Autodesk Fusion 360 part; units mm, degrees
(part 7 of 9)
equation "d858 = pcbRailThickness"
equation "d860 = pcbLeft + ( pcbWidth - pcbHolePitchX ) / 2 + 1 * pcbHolePitchX"
equation "d861 = pcbFront + ( pcbLength - pcbHolePitchY ) / 2 + 1 * pcbHolePitchY"
equation "d862 = pcbPostDiameter"
equation "d863 = pcbPostHeight"
equation "d865 = pcbLeft + ( pcbWidth - pcbHolePitchX ) / 2 + 1 * pcbHolePitchX"
equation "d866 = pcbFront + ( pcbLength - pcbHolePitchY ) / 2 + 1 * pcbHolePitchY"
equation "d867 = pcbPostPilot"
equation "holderStemX = -0.08972306 mm" comment "Fitted central cylinder X in original holder mesh"
equation "holderStemY = 1.49765268 mm" comment "Fitted central cylinder Y in original holder mesh"
equation "holderWidth = 11.03147984 mm" comment "Exact 3MF X bounding width"
equation "holderLength = 9.74910164 mm" comment "Exact 3MF Y bounding length"
equation "holderHeight = 5.2 mm" comment "Exact 3MF bounding height"
equation "holderTopDepth = shellWall + carrierClearance + 7 mm" comment "Measured flange underside to holder top"
equation "holderBottomDepth = holderTopDepth + holderHeight" comment "Holder lower bearing plane"
equation "holderFit = 0.2 mm" comment "Provisional XY pocket clearance per side"
equation "holderFrameX = 18.4 mm" comment "Receiver outer width"
equation "holderFrameY = 17.6 mm" comment "Receiver outer length preserving OLED clearance"
equation "holderSwitchVoid = 16 mm" comment "Provisional switch lower-body clearance"
equation "holderHookOverlap = 0.3 mm" comment "Prototype retention overlap"
equation "holderHookThickness = 0.8 mm" comment "Snap retaining lip thickness"
equation "holderSpringWidth = 2 mm" comment "External spring width"
equation "holderSpringY = 3.7 mm" comment "Mesh-verified plastic edge band clear of contact exits"
equation "holderLidGap = 0.2 mm" comment "Normal clearance between holder underside and lid support"
equation "d1834 = -( shellWall + carrierClearance + carrierThickness )"
equation "d1836 = -holderTopDepth"
equation "d1838 = -holderBottomDepth"
equation "d1840 = -( shellWall + carrierClearance + carrierThickness + 1 mm )"
equation "d1842 = -( holderBottomDepth + holderLidGap )"
equation "d1844 = bottomThickness"
equation "d1846 = ( layoutGap + keycapSize / 2 + 0 * keyPitch ) - holderFrameX / 2"
equation "d1847 = ( ( keyRowOne ) - holderFrameY / 2 ) + faceOriginV"
equation "d1848 = ( ( ( layoutGap + keycapSize / 2 + 0 * keyPitch ) - holderFrameX / 2 ) + ( holderFrameX ) ) - ( ( layoutGap + keycapSize / 2 + 0 * keyPitch ) - holderFrameX / 2 )"
equation "d1849 = ( ( ( ( keyRowOne ) - holderFrameY / 2 ) + faceOriginV ) + ( holderFrameY ) ) - ( ( ( keyRowOne ) - holderFrameY / 2 ) + faceOriginV )"
equation "d1850 = -( holderBottomDepth + holderHookThickness - shellWall - carrierClearance - carrierThickness )"
equation "d1852 = ( layoutGap + keycapSize / 2 + 0 * keyPitch ) - holderSwitchVoid / 2"
equation "d1853 = ( ( keyRowOne ) - holderSwitchVoid / 2 ) + faceOriginV"
equation "d1854 = ( ( ( layoutGap + keycapSize / 2 + 0 * keyPitch ) - holderSwitchVoid / 2 ) + ( holderSwitchVoid ) ) - ( ( layoutGap + keycapSize / 2 + 0 * keyPitch ) - holderSwitchVoid / 2 )"
equation "d1855 = ( ( ( ( keyRowOne ) - holderSwitchVoid / 2 ) + faceOriginV ) + ( holderSwitchVoid ) ) - ( ( ( keyRowOne ) - holderSwitchVoid / 2 ) + faceOriginV )"
equation "d1856 = -( holderTopDepth - shellWall - carrierClearance - carrierThickness )"
equation "d1858 = ( ( layoutGap + keycapSize / 2 + 0 * keyPitch ) - holderStemX ) - holderWidth / 2 - holderFit"
equation "d1859 = ( ( ( keyRowOne ) - holderStemY ) - holderLength / 2 - holderFit ) + faceOriginV"
equation "d1860 = ( ( ( ( layoutGap + keycapSize / 2 + 0 * keyPitch ) - holderStemX ) - holderWidth / 2 - holderFit ) + ( holderWidth + 2 * holderFit ) ) - ( ( ( layoutGap + keycapSize / 2 + 0 * keyPitch ) - holderStemX ) - holderWidth / 2 - holderFit )"
equation "d1861 = ( ( ( ( ( keyRowOne ) - holderStemY ) - holderLength / 2 - holderFit ) + faceOriginV ) + ( holderLength + 2 * holderFit ) ) - ( ( ( ( keyRowOne ) - holderStemY ) - holderLength / 2 - holderFit ) + faceOriginV )"
equation "d1862 = -( holderHeight + holderHookThickness + 0.2 mm )"
equation "d1864 = ( ( layoutGap + keycapSize / 2 + 0 * keyPitch ) - holderStemX ) - holderFrameX / 2 - 0.1 mm"
equation "d1865 = ( ( ( ( keyRowOne ) - holderStemY ) + holderSpringY ) - holderSpringWidth / 2 - 0.6 mm ) + faceOriginV"
equation "d1866 = ( ( ( ( layoutGap + keycapSize / 2 + 0 * keyPitch ) - holderStemX ) - holderFrameX / 2 - 0.1 mm ) + ( holderFrameX / 2 - holderWidth / 2 - holderFit + 0.1 mm ) ) - ( ( ( layoutGap + keycapSize / 2 + 0 * keyPitch ) - holderStemX ) - holderFrameX / 2 - 0.1 mm )"
equation "d1867 = ( ( ( ( ( ( keyRowOne ) - holderStemY ) + holderSpringY ) - holderSpringWidth / 2 - 0.6 mm ) + faceOriginV ) + ( 0.6 mm ) ) - ( ( ( ( ( keyRowOne ) - holderStemY ) + holderSpringY ) - holderSpringWidth / 2 - 0.6 mm ) + faceOriginV )"
equation "d1868 = -( holderBottomDepth + holderHookThickness - shellWall - carrierClearance - carrierThickness - 1 mm + 0.2 mm )"
equation "d1870 = ( ( layoutGap + keycapSize / 2 + 0 * keyPitch ) - holderStemX ) - holderFrameX / 2 - 0.1 mm"
equation "d1871 = ( ( ( ( keyRowOne ) - holderStemY ) + holderSpringY ) + holderSpringWidth / 2 ) + faceOriginV"
equation "d1872 = ( ( ( ( layoutGap + keycapSize / 2 + 0 * keyPitch ) - holderStemX ) - holderFrameX / 2 - 0.1 mm ) + ( holderFrameX / 2 - holderWidth / 2 - holderFit + 0.1 mm ) ) - ( ( ( layoutGap + keycapSize / 2 + 0 * keyPitch ) - holderStemX ) - holderFrameX / 2 - 0.1 mm )"
equation "d1873 = ( ( ( ( ( ( keyRowOne ) - holderStemY ) + holderSpringY ) + holderSpringWidth / 2 ) + faceOriginV ) + ( 0.6 mm ) ) - ( ( ( ( ( keyRowOne ) - holderStemY ) + holderSpringY ) + holderSpringWidth / 2 ) + faceOriginV )"
equation "d1874 = -( holderBottomDepth + holderHookThickness - shellWall - carrierClearance - carrierThickness - 1 mm + 0.2 mm )"
equation "d1876 = ( ( layoutGap + keycapSize / 2 + 0 * keyPitch ) - holderStemX ) - holderFrameX / 2 + 0.8 mm"
equation "d1877 = ( ( ( ( keyRowOne ) - holderStemY ) + holderSpringY ) - holderSpringWidth / 2 ) + faceOriginV"
equation "d1878 = ( ( ( ( layoutGap + keycapSize / 2 + 0 * keyPitch ) - holderStemX ) - holderFrameX / 2 + 0.8 mm ) + ( holderFrameX / 2 - 0.8 mm - holderWidth / 2 - holderFit ) ) - ( ( ( layoutGap + keycapSize / 2 + 0 * keyPitch ) - holderStemX ) - holderFrameX / 2 + 0.8 mm )"
equation "d1879 = ( ( ( ( ( ( keyRowOne ) - holderStemY ) + holderSpringY ) - holderSpringWidth / 2 ) + faceOriginV ) + ( holderSpringWidth ) ) - ( ( ( ( ( keyRowOne ) - holderStemY ) + holderSpringY ) - holderSpringWidth / 2 ) + faceOriginV )"
equation "d1880 = -( holderHeight + holderHookThickness + 0.2 mm )"
equation "d1882 = ( ( layoutGap + keycapSize / 2 + 0 * keyPitch ) - holderStemX ) - holderFrameX / 2"
equation "d1883 = ( ( ( ( keyRowOne ) - holderStemY ) + holderSpringY ) - holderSpringWidth / 2 ) + faceOriginV"
equation "d1884 = ( ( ( ( layoutGap + keycapSize / 2 + 0 * keyPitch ) - holderStemX ) - holderFrameX / 2 ) + ( holderFrameX / 2 - holderWidth / 2 + holderHookOverlap ) ) - ( ( ( layoutGap + keycapSize / 2 + 0 * keyPitch ) - holderStemX ) - holderFrameX / 2 )"
equation "d1885 = ( ( ( ( ( ( keyRowOne ) - holderStemY ) + holderSpringY ) - holderSpringWidth / 2 ) + faceOriginV ) + ( holderSpringWidth ) ) - ( ( ( ( ( keyRowOne ) - holderStemY ) + holderSpringY ) - holderSpringWidth / 2 ) + faceOriginV )"
equation "d1886 = -( holderHookThickness )"
equation "d1889 = ( ( layoutGap + keycapSize / 2 + 0 * keyPitch ) - holderStemX ) + holderWidth / 2 + holderFit"
equation "d1890 = ( ( ( ( keyRowOne ) - holderStemY ) + holderSpringY ) - holderSpringWidth / 2 - 0.6 mm ) + faceOriginV"
equation "d1891 = ( ( ( ( layoutGap + keycapSize / 2 + 0 * keyPitch ) - holderStemX ) + holderWidth / 2 + holderFit ) + ( holderFrameX / 2 - holderWidth / 2 - holderFit + 0.1 mm ) ) - ( ( ( layoutGap + keycapSize / 2 + 0 * keyPitch ) - holderStemX ) + holderWidth / 2 + holderFit )"
equation "d1892 = ( ( ( ( ( ( keyRowOne ) - holderStemY ) + holderSpringY ) - holderSpringWidth / 2 - 0.6 mm ) + faceOriginV ) + ( 0.6 mm ) ) - ( ( ( ( ( keyRowOne ) - holderStemY ) + holderSpringY ) - holderSpringWidth / 2 - 0.6 mm ) + faceOriginV )"
equation "d1893 = -( holderBottomDepth + holderHookThickness - shellWall - carrierClearance - carrierThickness - 1 mm + 0.2 mm )"
equation "d1895 = ( ( layoutGap + keycapSize / 2 + 0 * keyPitch ) - holderStemX ) + holderWidth / 2 + holderFit"
equation "d1896 = ( ( ( ( keyRowOne ) - holderStemY ) + holderSpringY ) + holderSpringWidth / 2 ) + faceOriginV"
equation "d1897 = ( ( ( ( layoutGap + keycapSize / 2 + 0 * keyPitch ) - holderStemX ) + holderWidth / 2 + holderFit ) + ( holderFrameX / 2 - holderWidth / 2 - holderFit + 0.1 mm ) ) - ( ( ( layoutGap + keycapSize / 2 + 0 * keyPitch ) - holderStemX ) + holderWidth / 2 + holderFit )"
equation "d1898 = ( ( ( ( ( ( keyRowOne ) - holderStemY ) + holderSpringY ) + holderSpringWidth / 2 ) + faceOriginV ) + ( 0.6 mm ) ) - ( ( ( ( ( keyRowOne ) - holderStemY ) + holderSpringY ) + holderSpringWidth / 2 ) + faceOriginV )"
equation "d1899 = -( holderBottomDepth + holderHookThickness - shellWall - carrierClearance - carrierThickness - 1 mm + 0.2 mm )"
equation "d1901 = ( ( layoutGap + keycapSize / 2 + 0 * keyPitch ) - holderStemX ) + holderWidth / 2 + holderFit"
equation "d1902 = ( ( ( ( keyRowOne ) - holderStemY ) + holderSpringY ) - holderSpringWidth / 2 ) + faceOriginV"
equation "d1903 = ( ( ( ( layoutGap + keycapSize / 2 + 0 * keyPitch ) - holderStemX ) + holderWidth / 2 + holderFit ) + ( holderFrameX / 2 - 0.8 mm - holderWidth / 2 - holderFit ) ) - ( ( ( layoutGap + keycapSize / 2 + 0 * keyPitch ) - holderStemX ) + holderWidth / 2 + holderFit )"
equation "d1904 = ( ( ( ( ( ( keyRowOne ) - holderStemY ) + holderSpringY ) - holderSpringWidth / 2 ) + faceOriginV ) + ( holderSpringWidth ) ) - ( ( ( ( ( keyRowOne ) - holderStemY ) + holderSpringY ) - holderSpringWidth / 2 ) + faceOriginV )"
equation "d1905 = -( holderHeight + holderHookThickness + 0.2 mm )"
equation "d1907 = ( ( layoutGap + keycapSize / 2 + 0 * keyPitch ) - holderStemX ) + holderWidth / 2 - holderHookOverlap"
equation "d1908 = ( ( ( ( keyRowOne ) - holderStemY ) + holderSpringY ) - holderSpringWidth / 2 ) + faceOriginV"
equation "d1909 = ( ( ( ( layoutGap + keycapSize / 2 + 0 * keyPitch ) - holderStemX ) + holderWidth / 2 - holderHookOverlap ) + ( holderFrameX / 2 - holderWidth / 2 + holderHookOverlap ) ) - ( ( ( layoutGap + keycapSize / 2 + 0 * keyPitch ) - holderStemX ) + holderWidth / 2 - holderHookOverlap )"
equation "d1910 = ( ( ( ( ( ( keyRowOne ) - holderStemY ) + holderSpringY ) - holderSpringWidth / 2 ) + faceOriginV ) + ( holderSpringWidth ) ) - ( ( ( ( ( keyRowOne ) - holderStemY ) + holderSpringY ) - holderSpringWidth / 2 ) + faceOriginV )"
equation "d1911 = -( holderHookThickness )"
equation "d1914 = ( ( layoutGap + keycapSize / 2 + 0 * keyPitch ) - holderStemX ) + ( -3 mm ) - 0.5 mm"
equation "d1915 = ( ( ( keyRowOne ) - holderStemY ) + 4 mm ) + faceOriginV"
equation "d1916 = ( ( ( ( layoutGap + keycapSize / 2 + 0 * keyPitch ) - holderStemX ) + ( -3 mm ) - 0.5 mm ) + ( 1 mm ) ) - ( ( ( layoutGap + keycapSize / 2 + 0 * keyPitch ) - holderStemX ) + ( -3 mm ) - 0.5 mm )"
equation "d1917 = ( ( ( ( ( keyRowOne ) - holderStemY ) + 4 mm ) + faceOriginV ) + ( holderFrameY / 2 - 4 mm ) ) - ( ( ( ( keyRowOne ) - holderStemY ) + 4 mm ) + faceOriginV )"
equation "d1920 = ( ( layoutGap + keycapSize / 2 + 0 * keyPitch ) - holderStemX ) + ( 3 mm ) - 0.5 mm"
equation "d1921 = ( ( ( keyRowOne ) - holderStemY ) + 4 mm ) + faceOriginV"
equation "d1922 = ( ( ( ( layoutGap + keycapSize / 2 + 0 * keyPitch ) - holderStemX ) + ( 3 mm ) - 0.5 mm ) + ( 1 mm ) ) - ( ( ( layoutGap + keycapSize / 2 + 0 * keyPitch ) - holderStemX ) + ( 3 mm ) - 0.5 mm )"
equation "d1923 = ( ( ( ( ( keyRowOne ) - holderStemY ) + 4 mm ) + faceOriginV ) + ( holderFrameY / 2 - 4 mm ) ) - ( ( ( ( keyRowOne ) - holderStemY ) + 4 mm ) + faceOriginV )"
equation "d1928 = ( ( layoutGap + keycapSize / 2 + 0 * keyPitch ) - holderStemX ) - holderFrameX / 2 - 0.1 mm"
equation "d1929 = ( ( ( keyRowOne ) - holderStemY ) - 5.1 mm ) + faceOriginV"
equation "d1930 = ( ( ( ( layoutGap + keycapSize / 2 + 0 * keyPitch ) - holderStemX ) - holderFrameX / 2 - 0.1 mm ) + ( holderFrameX / 2 - holderWidth / 2 + 0.1 mm ) ) - ( ( ( layoutGap + keycapSize / 2 + 0 * keyPitch ) - holderStemX ) - holderFrameX / 2 - 0.1 mm )"
equation "d1931 = ( ( ( ( ( keyRowOne ) - holderStemY ) - 5.1 mm ) + faceOriginV ) + ( 7.8 mm ) ) - ( ( ( ( keyRowOne ) - holderStemY ) - 5.1 mm ) + faceOriginV )"
equation "d1932 = -( holderHeight + holderHookThickness - 1.2 mm + 0.2 mm )"
equation "d1934 = ( ( layoutGap + keycapSize / 2 + 0 * keyPitch ) - holderStemX ) + holderWidth / 2"
equation "d1935 = ( ( ( keyRowOne ) - holderStemY ) - 5.1 mm ) + faceOriginV"
equation "d1936 = ( ( ( ( layoutGap + keycapSize / 2 + 0 * keyPitch ) - holderStemX ) + holderWidth / 2 ) + ( holderFrameX / 2 - holderWidth / 2 + 0.1 mm ) ) - ( ( ( layoutGap + keycapSize / 2 + 0 * keyPitch ) - holderStemX ) + holderWidth / 2 )"
equation "d1937 = ( ( ( ( ( keyRowOne ) - holderStemY ) - 5.1 mm ) + faceOriginV ) + ( 7.8 mm ) ) - ( ( ( ( keyRowOne ) - holderStemY ) - 5.1 mm ) + faceOriginV )"
equation "d1938 = -( holderHeight + holderHookThickness - 1.2 mm + 0.2 mm )"
equation "d1940 = ( ( layoutGap + keycapSize / 2 + 0 * keyPitch ) - holderStemX ) + ( -2.5 mm ) - 1.2 mm"
equation "d1941 = ( ( ( ( keyRowOne ) - holderStemY ) - 1.2 mm ) * cos(caseTilt) + ( holderBottomDepth + holderLidGap ) * sin(caseTilt) ) - 2.5 mm"
equation "d1942 = ( ( ( ( layoutGap + keycapSize / 2 + 0 * keyPitch ) - holderStemX ) + ( -2.5 mm ) - 1.2 mm ) + ( 2.4 mm ) ) - ( ( ( layoutGap + keycapSize / 2 + 0 * keyPitch ) - holderStemX ) + ( -2.5 mm ) - 1.2 mm )"
equation "d1943 = ( ( ( ( ( ( keyRowOne ) - holderStemY ) - 1.2 mm ) * cos(caseTilt) + ( holderBottomDepth + holderLidGap ) * sin(caseTilt) ) - 2.5 mm ) + ( 5 mm ) ) - ( ( ( ( ( keyRowOne ) - holderStemY ) - 1.2 mm ) * cos(caseTilt) + ( holderBottomDepth + holderLidGap ) * sin(caseTilt) ) - 2.5 mm )"
equation "d1944 = ( frontHeight + ( ( ( keyRowOne ) - holderStemY ) - 1.2 mm ) * sin(caseTilt) - ( holderBottomDepth + holderLidGap ) * cos(caseTilt) ) - bottomThickness - 2 mm"
equation "d1946 = ( ( layoutGap + keycapSize / 2 + 0 * keyPitch ) - holderStemX ) + ( -2.5 mm ) - 0.5 mm"
equation "d1947 = ( ( ( ( keyRowOne ) - holderStemY ) - 1.2 mm ) * cos(caseTilt) + ( holderBottomDepth + holderLidGap ) * sin(caseTilt) ) - 1.5 mm"
equation "d1948 = ( ( ( ( layoutGap + keycapSize / 2 + 0 * keyPitch ) - holderStemX ) + ( -2.5 mm ) - 0.5 mm ) + ( 1 mm ) ) - ( ( ( layoutGap + keycapSize / 2 + 0 * keyPitch ) - holderStemX ) + ( -2.5 mm ) - 0.5 mm )"
equation "d1949 = ( ( ( ( ( ( keyRowOne ) - holderStemY ) - 1.2 mm ) * cos(caseTilt) + ( holderBottomDepth + holderLidGap ) * sin(caseTilt) ) - 1.5 mm ) + ( 3 mm ) ) - ( ( ( ( ( keyRowOne ) - holderStemY ) - 1.2 mm ) * cos(caseTilt) + ( holderBottomDepth + holderLidGap ) * sin(caseTilt) ) - 1.5 mm )"
equation "d1950 = ( frontHeight + ( ( ( keyRowOne ) - holderStemY ) - 1.2 mm ) * sin(caseTilt) - ( holderBottomDepth + holderLidGap ) * cos(caseTilt) ) - bottomThickness + 0.5 mm"
equation "d1952 = ( ( ( layoutGap + keycapSize / 2 + 0 * keyPitch ) - holderStemX ) + ( -2.5 mm ) - 0.5 mm ) - 0.1 mm"
equation "d1953 = ( ( ( ( keyRowOne ) - holderStemY ) - 1.2 mm ) - 2 mm ) + faceOriginV"
equation "d1954 = ( ( ( ( ( layoutGap + keycapSize / 2 + 0 * keyPitch ) - holderStemX ) + ( -2.5 mm ) - 0.5 mm ) - 0.1 mm ) + ( 1.2 mm ) ) - ( ( ( ( layoutGap + keycapSize / 2 + 0 * keyPitch ) - holderStemX ) + ( -2.5 mm ) - 0.5 mm ) - 0.1 mm )"
equation "d1955 = ( ( ( ( ( ( keyRowOne ) - holderStemY ) - 1.2 mm ) - 2 mm ) + faceOriginV ) + ( 4 mm ) ) - ( ( ( ( ( keyRowOne ) - holderStemY ) - 1.2 mm ) - 2 mm ) + faceOriginV )"
equation "d1956 = rearHeight"
equation "d1958 = ( ( layoutGap + keycapSize / 2 + 0 * keyPitch ) - holderStemX ) + ( 2.5 mm ) - 1.2 mm"
equation "d1959 = ( ( ( ( keyRowOne ) - holderStemY ) - 1.2 mm ) * cos(caseTilt) + ( holderBottomDepth + holderLidGap ) * sin(caseTilt) ) - 2.5 mm"
equation "d1960 = ( ( ( ( layoutGap + keycapSize / 2 + 0 * keyPitch ) - holderStemX ) + ( 2.5 mm ) - 1.2 mm ) + ( 2.4 mm ) ) - ( ( ( layoutGap + keycapSize / 2 + 0 * keyPitch ) - holderStemX ) + ( 2.5 mm ) - 1.2 mm )"
equation "d1961 = ( ( ( ( ( ( keyRowOne ) - holderStemY ) - 1.2 mm ) * cos(caseTilt) + ( holderBottomDepth + holderLidGap ) * sin(caseTilt) ) - 2.5 mm ) + ( 5 mm ) ) - ( ( ( ( ( keyRowOne ) - holderStemY ) - 1.2 mm ) * cos(caseTilt) + ( holderBottomDepth + holderLidGap ) * sin(caseTilt) ) - 2.5 mm )"
equation "d1962 = ( frontHeight + ( ( ( keyRowOne ) - holderStemY ) - 1.2 mm ) * sin(caseTilt) - ( holderBottomDepth + holderLidGap ) * cos(caseTilt) ) - bottomThickness - 2 mm"
equation "d1964 = ( ( layoutGap + keycapSize / 2 + 0 * keyPitch ) - holderStemX ) + ( 2.5 mm ) - 0.5 mm"
equation "d1965 = ( ( ( ( keyRowOne ) - holderStemY ) - 1.2 mm ) * cos(caseTilt) + ( holderBottomDepth + holderLidGap ) * sin(caseTilt) ) - 1.5 mm"
equation "d1966 = ( ( ( ( layoutGap + keycapSize / 2 + 0 * keyPitch ) - holderStemX ) + ( 2.5 mm ) - 0.5 mm ) + ( 1 mm ) ) - ( ( ( layoutGap + keycapSize / 2 + 0 * keyPitch ) - holderStemX ) + ( 2.5 mm ) - 0.5 mm )"
equation "d1967 = ( ( ( ( ( ( keyRowOne ) - holderStemY ) - 1.2 mm ) * cos(caseTilt) + ( holderBottomDepth + holderLidGap ) * sin(caseTilt) ) - 1.5 mm ) + ( 3 mm ) ) - ( ( ( ( ( keyRowOne ) - holderStemY ) - 1.2 mm ) * cos(caseTilt) + ( holderBottomDepth + holderLidGap ) * sin(caseTilt) ) - 1.5 mm )"
equation "d1968 = ( frontHeight + ( ( ( keyRowOne ) - holderStemY ) - 1.2 mm ) * sin(caseTilt) - ( holderBottomDepth + holderLidGap ) * cos(caseTilt) ) - bottomThickness + 0.5 mm"
equation "d1970 = ( ( ( layoutGap + keycapSize / 2 + 0 * keyPitch ) - holderStemX ) + ( 2.5 mm ) - 0.5 mm ) - 0.1 mm"
equation "d1971 = ( ( ( ( keyRowOne ) - holderStemY ) - 1.2 mm ) - 2 mm ) + faceOriginV"
equation "d1972 = ( ( ( ( ( layoutGap + keycapSize / 2 + 0 * keyPitch ) - holderStemX ) + ( 2.5 mm ) - 0.5 mm ) - 0.1 mm ) + ( 1.2 mm ) ) - ( ( ( ( layoutGap + keycapSize / 2 + 0 * keyPitch ) - holderStemX ) + ( 2.5 mm ) - 0.5 mm ) - 0.1 mm )"
equation "d1973 = ( ( ( ( ( ( keyRowOne ) - holderStemY ) - 1.2 mm ) - 2 mm ) + faceOriginV ) + ( 4 mm ) ) - ( ( ( ( ( keyRowOne ) - holderStemY ) - 1.2 mm ) - 2 mm ) + faceOriginV )"
equation "d1974 = rearHeight"
equation "d1976 = ( layoutGap + keycapSize / 2 + 1 * keyPitch ) - holderFrameX / 2"
equation "d1977 = ( ( keyRowOne ) - holderFrameY / 2 ) + faceOriginV"
equation "d1978 = ( ( ( layoutGap + keycapSize / 2 + 1 * keyPitch ) - holderFrameX / 2 ) + ( holderFrameX ) ) - ( ( layoutGap + keycapSize / 2 + 1 * keyPitch ) - holderFrameX / 2 )"
equation "d1979 = ( ( ( ( keyRowOne ) - holderFrameY / 2 ) + faceOriginV ) + ( holderFrameY ) ) - ( ( ( keyRowOne ) - holderFrameY / 2 ) + faceOriginV )"
equation "d1980 = -( holderBottomDepth + holderHookThickness - shellWall - carrierClearance - carrierThickness )"
equation "d1982 = ( layoutGap + keycapSize / 2 + 1 * keyPitch ) - holderSwitchVoid / 2"
equation "d1983 = ( ( keyRowOne ) - holderSwitchVoid / 2 ) + faceOriginV"
equation "d1984 = ( ( ( layoutGap + keycapSize / 2 + 1 * keyPitch ) - holderSwitchVoid / 2 ) + ( holderSwitchVoid ) ) - ( ( layoutGap + keycapSize / 2 + 1 * keyPitch ) - holderSwitchVoid / 2 )"
equation "d1985 = ( ( ( ( keyRowOne ) - holderSwitchVoid / 2 ) + faceOriginV ) + ( holderSwitchVoid ) ) - ( ( ( keyRowOne ) - holderSwitchVoid / 2 ) + faceOriginV )"
equation "d1986 = -( holderTopDepth - shellWall - carrierClearance - carrierThickness )"
equation "d1988 = ( ( layoutGap + keycapSize / 2 + 1 * keyPitch ) - holderStemX ) - holderWidth / 2 - holderFit"
equation "d1989 = ( ( ( keyRowOne ) - holderStemY ) - holderLength / 2 - holderFit ) + faceOriginV"
equation "d1990 = ( ( ( ( layoutGap + keycapSize / 2 + 1 * keyPitch ) - holderStemX ) - holderWidth / 2 - holderFit ) + ( holderWidth + 2 * holderFit ) ) - ( ( ( layoutGap + keycapSize / 2 + 1 * keyPitch ) - holderStemX ) - holderWidth / 2 - holderFit )"
equation "d1991 = ( ( ( ( ( keyRowOne ) - holderStemY ) - holderLength / 2 - holderFit ) + faceOriginV ) + ( holderLength + 2 * holderFit ) ) - ( ( ( ( keyRowOne ) - holderStemY ) - holderLength / 2 - holderFit ) + faceOriginV )"
equation "d1992 = -( holderHeight + holderHookThickness + 0.2 mm )"
equation "d1994 = ( ( layoutGap + keycapSize / 2 + 1 * keyPitch ) - holderStemX ) - holderFrameX / 2 - 0.1 mm"
equation "d1995 = ( ( ( ( keyRowOne ) - holderStemY ) + holderSpringY ) - holderSpringWidth / 2 - 0.6 mm ) + faceOriginV"
equation "d1996 = ( ( ( ( layoutGap + keycapSize / 2 + 1 * keyPitch ) - holderStemX ) - holderFrameX / 2 - 0.1 mm ) + ( holderFrameX / 2 - holderWidth / 2 - holderFit + 0.1 mm ) ) - ( ( ( layoutGap + keycapSize / 2 + 1 * keyPitch ) - holderStemX ) - holderFrameX / 2 - 0.1 mm )"
equation "d1997 = ( ( ( ( ( ( keyRowOne ) - holderStemY ) + holderSpringY ) - holderSpringWidth / 2 - 0.6 mm ) + faceOriginV ) + ( 0.6 mm ) ) - ( ( ( ( ( keyRowOne ) - holderStemY ) + holderSpringY ) - holderSpringWidth / 2 - 0.6 mm ) + faceOriginV )"
equation "d1998 = -( holderBottomDepth + holderHookThickness - shellWall - carrierClearance - carrierThickness - 1 mm + 0.2 mm )"
equation "d2000 = ( ( layoutGap + keycapSize / 2 + 1 * keyPitch ) - holderStemX ) - holderFrameX / 2 - 0.1 mm"
equation "d2001 = ( ( ( ( keyRowOne ) - holderStemY ) + holderSpringY ) + holderSpringWidth / 2 ) + faceOriginV"
equation "d2002 = ( ( ( ( layoutGap + keycapSize / 2 + 1 * keyPitch ) - holderStemX ) - holderFrameX / 2 - 0.1 mm ) + ( holderFrameX / 2 - holderWidth / 2 - holderFit + 0.1 mm ) ) - ( ( ( layoutGap + keycapSize / 2 + 1 * keyPitch ) - holderStemX ) - holderFrameX / 2 - 0.1 mm )"
equation "d2003 = ( ( ( ( ( ( keyRowOne ) - holderStemY ) + holderSpringY ) + holderSpringWidth / 2 ) + faceOriginV ) + ( 0.6 mm ) ) - ( ( ( ( ( keyRowOne ) - holderStemY ) + holderSpringY ) + holderSpringWidth / 2 ) + faceOriginV )"
equation "d2004 = -( holderBottomDepth + holderHookThickness - shellWall - carrierClearance - carrierThickness - 1 mm + 0.2 mm )"
equation "d2006 = ( ( layoutGap + keycapSize / 2 + 1 * keyPitch ) - holderStemX ) - holderFrameX / 2 + 0.8 mm"
equation "d2007 = ( ( ( ( keyRowOne ) - holderStemY ) + holderSpringY ) - holderSpringWidth / 2 ) + faceOriginV"
equation "d2008 = ( ( ( ( layoutGap + keycapSize / 2 + 1 * keyPitch ) - holderStemX ) - holderFrameX / 2 + 0.8 mm ) + ( holderFrameX / 2 - 0.8 mm - holderWidth / 2 - holderFit ) ) - ( ( ( layoutGap + keycapSize / 2 + 1 * keyPitch ) - holderStemX ) - holderFrameX / 2 + 0.8 mm )"
equation "d2009 = ( ( ( ( ( ( keyRowOne ) - holderStemY ) + holderSpringY ) - holderSpringWidth / 2 ) + faceOriginV ) + ( holderSpringWidth ) ) - ( ( ( ( ( keyRowOne ) - holderStemY ) + holderSpringY ) - holderSpringWidth / 2 ) + faceOriginV )"
equation "d2010 = -( holderHeight + holderHookThickness + 0.2 mm )"
equation "d2012 = ( ( layoutGap + keycapSize / 2 + 1 * keyPitch ) - holderStemX ) - holderFrameX / 2"
equation "d2013 = ( ( ( ( keyRowOne ) - holderStemY ) + holderSpringY ) - holderSpringWidth / 2 ) + faceOriginV"
equation "d2014 = ( ( ( ( layoutGap + keycapSize / 2 + 1 * keyPitch ) - holderStemX ) - holderFrameX / 2 ) + ( holderFrameX / 2 - holderWidth / 2 + holderHookOverlap ) ) - ( ( ( layoutGap + keycapSize / 2 + 1 * keyPitch ) - holderStemX ) - holderFrameX / 2 )"
equation "d2015 = ( ( ( ( ( ( keyRowOne ) - holderStemY ) + holderSpringY ) - holderSpringWidth / 2 ) + faceOriginV ) + ( holderSpringWidth ) ) - ( ( ( ( ( keyRowOne ) - holderStemY ) + holderSpringY ) - holderSpringWidth / 2 ) + faceOriginV )"
equation "d2016 = -( holderHookThickness )"
equation "d2019 = ( ( layoutGap + keycapSize / 2 + 1 * keyPitch ) - holderStemX ) + holderWidth / 2 + holderFit"
equation "d2020 = ( ( ( ( keyRowOne ) - holderStemY ) + holderSpringY ) - holderSpringWidth / 2 - 0.6 mm ) + faceOriginV"
equation "d2021 = ( ( ( ( layoutGap + keycapSize / 2 + 1 * keyPitch ) - holderStemX ) + holderWidth / 2 + holderFit ) + ( holderFrameX / 2 - holderWidth / 2 - holderFit + 0.1 mm ) ) - ( ( ( layoutGap + keycapSize / 2 + 1 * keyPitch ) - holderStemX ) + holderWidth / 2 + holderFit )"
equation "d2022 = ( ( ( ( ( ( keyRowOne ) - holderStemY ) + holderSpringY ) - holderSpringWidth / 2 - 0.6 mm ) + faceOriginV ) + ( 0.6 mm ) ) - ( ( ( ( ( keyRowOne ) - holderStemY ) + holderSpringY ) - holderSpringWidth / 2 - 0.6 mm ) + faceOriginV )"
equation "d2023 = -( holderBottomDepth + holderHookThickness - shellWall - carrierClearance - carrierThickness - 1 mm + 0.2 mm )"
equation "d2025 = ( ( layoutGap + keycapSize / 2 + 1 * keyPitch ) - holderStemX ) + holderWidth / 2 + holderFit"
equation "d2026 = ( ( ( ( keyRowOne ) - holderStemY ) + holderSpringY ) + holderSpringWidth / 2 ) + faceOriginV"
equation "d2027 = ( ( ( ( layoutGap + keycapSize / 2 + 1 * keyPitch ) - holderStemX ) + holderWidth / 2 + holderFit ) + ( holderFrameX / 2 - holderWidth / 2 - holderFit + 0.1 mm ) ) - ( ( ( layoutGap + keycapSize / 2 + 1 * keyPitch ) - holderStemX ) + holderWidth / 2 + holderFit )"
equation "d2028 = ( ( ( ( ( ( keyRowOne ) - holderStemY ) + holderSpringY ) + holderSpringWidth / 2 ) + faceOriginV ) + ( 0.6 mm ) ) - ( ( ( ( ( keyRowOne ) - holderStemY ) + holderSpringY ) + holderSpringWidth / 2 ) + faceOriginV )"
equation "d2029 = -( holderBottomDepth + holderHookThickness - shellWall - carrierClearance - carrierThickness - 1 mm + 0.2 mm )"
equation "d2031 = ( ( layoutGap + keycapSize / 2 + 1 * keyPitch ) - holderStemX ) + holderWidth / 2 + holderFit"
equation "d2032 = ( ( ( ( keyRowOne ) - holderStemY ) + holderSpringY ) - holderSpringWidth / 2 ) + faceOriginV"
equation "d2033 = ( ( ( ( layoutGap + keycapSize / 2 + 1 * keyPitch ) - holderStemX ) + holderWidth / 2 + holderFit ) + ( holderFrameX / 2 - 0.8 mm - holderWidth / 2 - holderFit ) ) - ( ( ( layoutGap + keycapSize / 2 + 1 * keyPitch ) - holderStemX ) + holderWidth / 2 + holderFit )"
equation "d2034 = ( ( ( ( ( ( keyRowOne ) - holderStemY ) + holderSpringY ) - holderSpringWidth / 2 ) + faceOriginV ) + ( holderSpringWidth ) ) - ( ( ( ( ( keyRowOne ) - holderStemY ) + holderSpringY ) - holderSpringWidth / 2 ) + faceOriginV )"
equation "d2035 = -( holderHeight + holderHookThickness + 0.2 mm )"
equation "d2037 = ( ( layoutGap + keycapSize / 2 + 1 * keyPitch ) - holderStemX ) + holderWidth / 2 - holderHookOverlap"
equation "d2038 = ( ( ( ( keyRowOne ) - holderStemY ) + holderSpringY ) - holderSpringWidth / 2 ) + faceOriginV"
equation "d2039 = ( ( ( ( layoutGap + keycapSize / 2 + 1 * keyPitch ) - holderStemX ) + holderWidth / 2 - holderHookOverlap ) + ( holderFrameX / 2 - holderWidth / 2 + holderHookOverlap ) ) - ( ( ( layoutGap + keycapSize / 2 + 1 * keyPitch ) - holderStemX ) + holderWidth / 2 - holderHookOverlap )"
equation "d2040 = ( ( ( ( ( ( keyRowOne ) - holderStemY ) + holderSpringY ) - holderSpringWidth / 2 ) + faceOriginV ) + ( holderSpringWidth ) ) - ( ( ( ( ( keyRowOne ) - holderStemY ) + holderSpringY ) - holderSpringWidth / 2 ) + faceOriginV )"
equation "d2041 = -( holderHookThickness )"
equation "d2044 = ( ( layoutGap + keycapSize / 2 + 1 * keyPitch ) - holderStemX ) + ( -3 mm ) - 0.5 mm"
equation "d2045 = ( ( ( keyRowOne ) - holderStemY ) + 4 mm ) + faceOriginV"
equation "d2046 = ( ( ( ( layoutGap + keycapSize / 2 + 1 * keyPitch ) - holderStemX ) + ( -3 mm ) - 0.5 mm ) + ( 1 mm ) ) - ( ( ( layoutGap + keycapSize / 2 + 1 * keyPitch ) - holderStemX ) + ( -3 mm ) - 0.5 mm )"
equation "d2047 = ( ( ( ( ( keyRowOne ) - holderStemY ) + 4 mm ) + faceOriginV ) + ( holderFrameY / 2 - 4 mm ) ) - ( ( ( ( keyRowOne ) - holderStemY ) + 4 mm ) + faceOriginV )"
equation "d2050 = ( ( layoutGap + keycapSize / 2 + 1 * keyPitch ) - holderStemX ) + ( 3 mm ) - 0.5 mm"
equation "d2051 = ( ( ( keyRowOne ) - holderStemY ) + 4 mm ) + faceOriginV"
equation "d2052 = ( ( ( ( layoutGap + keycapSize / 2 + 1 * keyPitch ) - holderStemX ) + ( 3 mm ) - 0.5 mm ) + ( 1 mm ) ) - ( ( ( layoutGap + keycapSize / 2 + 1 * keyPitch ) - holderStemX ) + ( 3 mm ) - 0.5 mm )"
equation "d2053 = ( ( ( ( ( keyRowOne ) - holderStemY ) + 4 mm ) + faceOriginV ) + ( holderFrameY / 2 - 4 mm ) ) - ( ( ( ( keyRowOne ) - holderStemY ) + 4 mm ) + faceOriginV )"
equation "d2056 = ( ( layoutGap + keycapSize / 2 + 1 * keyPitch ) - holderStemX ) - holderFrameX / 2 - 0.1 mm"
equation "d2057 = ( ( ( keyRowOne ) - holderStemY ) - 5.1 mm ) + faceOriginV"
equation "d2058 = ( ( ( ( layoutGap + keycapSize / 2 + 1 * keyPitch ) - holderStemX ) - holderFrameX / 2 - 0.1 mm ) + ( holderFrameX / 2 - holderWidth / 2 + 0.1 mm ) ) - ( ( ( layoutGap + keycapSize / 2 + 1 * keyPitch ) - holderStemX ) - holderFrameX / 2 - 0.1 mm )"
equation "d2059 = ( ( ( ( ( keyRowOne ) - holderStemY ) - 5.1 mm ) + faceOriginV ) + ( 7.8 mm ) ) - ( ( ( ( keyRowOne ) - holderStemY ) - 5.1 mm ) + faceOriginV )"
equation "d2060 = -( holderHeight + holderHookThickness - 1.2 mm + 0.2 mm )"
equation "d2062 = ( ( layoutGap + keycapSize / 2 + 1 * keyPitch ) - holderStemX ) + holderWidth / 2"
equation "d2063 = ( ( ( keyRowOne ) - holderStemY ) - 5.1 mm ) + faceOriginV"
equation "d2064 = ( ( ( ( layoutGap + keycapSize / 2 + 1 * keyPitch ) - holderStemX ) + holderWidth / 2 ) + ( holderFrameX / 2 - holderWidth / 2 + 0.1 mm ) ) - ( ( ( layoutGap + keycapSize / 2 + 1 * keyPitch ) - holderStemX ) + holderWidth / 2 )"
equation "d2065 = ( ( ( ( ( keyRowOne ) - holderStemY ) - 5.1 mm ) + faceOriginV ) + ( 7.8 mm ) ) - ( ( ( ( keyRowOne ) - holderStemY ) - 5.1 mm ) + faceOriginV )"
equation "d2066 = -( holderHeight + holderHookThickness - 1.2 mm + 0.2 mm )"
equation "d2068 = ( ( layoutGap + keycapSize / 2 + 1 * keyPitch ) - holderStemX ) + ( -2.5 mm ) - 1.2 mm"
equation "d2069 = ( ( ( ( keyRowOne ) - holderStemY ) - 1.2 mm ) * cos(caseTilt) + ( holderBottomDepth + holderLidGap ) * sin(caseTilt) ) - 2.5 mm"
equation "d2070 = ( ( ( ( layoutGap + keycapSize / 2 + 1 * keyPitch ) - holderStemX ) + ( -2.5 mm ) - 1.2 mm ) + ( 2.4 mm ) ) - ( ( ( layoutGap + keycapSize / 2 + 1 * keyPitch ) - holderStemX ) + ( -2.5 mm ) - 1.2 mm )"
equation "d2071 = ( ( ( ( ( ( keyRowOne ) - holderStemY ) - 1.2 mm ) * cos(caseTilt) + ( holderBottomDepth + holderLidGap ) * sin(caseTilt) ) - 2.5 mm ) + ( 5 mm ) ) - ( ( ( ( ( keyRowOne ) - holderStemY ) - 1.2 mm ) * cos(caseTilt) + ( holderBottomDepth + holderLidGap ) * sin(caseTilt) ) - 2.5 mm )"
equation "d2072 = ( frontHeight + ( ( ( keyRowOne ) - holderStemY ) - 1.2 mm ) * sin(caseTilt) - ( holderBottomDepth + holderLidGap ) * cos(caseTilt) ) - bottomThickness - 2 mm"
equation "d2074 = ( ( layoutGap + keycapSize / 2 + 1 * keyPitch ) - holderStemX ) + ( -2.5 mm ) - 0.5 mm"
equation "d2075 = ( ( ( ( keyRowOne ) - holderStemY ) - 1.2 mm ) * cos(caseTilt) + ( holderBottomDepth + holderLidGap ) * sin(caseTilt) ) - 1.5 mm"
equation "d2076 = ( ( ( ( layoutGap + keycapSize / 2 + 1 * keyPitch ) - holderStemX ) + ( -2.5 mm ) - 0.5 mm ) + ( 1 mm ) ) - ( ( ( layoutGap + keycapSize / 2 + 1 * keyPitch ) - holderStemX ) + ( -2.5 mm ) - 0.5 mm )"
equation "d2077 = ( ( ( ( ( ( keyRowOne ) - holderStemY ) - 1.2 mm ) * cos(caseTilt) + ( holderBottomDepth + holderLidGap ) * sin(caseTilt) ) - 1.5 mm ) + ( 3 mm ) ) - ( ( ( ( ( keyRowOne ) - holderStemY ) - 1.2 mm ) * cos(caseTilt) + ( holderBottomDepth + holderLidGap ) * sin(caseTilt) ) - 1.5 mm )"
equation "d2078 = ( frontHeight + ( ( ( keyRowOne ) - holderStemY ) - 1.2 mm ) * sin(caseTilt) - ( holderBottomDepth + holderLidGap ) * cos(caseTilt) ) - bottomThickness + 0.5 mm"
equation "d2080 = ( ( ( layoutGap + keycapSize / 2 + 1 * keyPitch ) - holderStemX ) + ( -2.5 mm ) - 0.5 mm ) - 0.1 mm"
equation "d2081 = ( ( ( ( keyRowOne ) - holderStemY ) - 1.2 mm ) - 2 mm ) + faceOriginV"
equation "d2082 = ( ( ( ( ( layoutGap + keycapSize / 2 + 1 * keyPitch ) - holderStemX ) + ( -2.5 mm ) - 0.5 mm ) - 0.1 mm ) + ( 1.2 mm ) ) - ( ( ( ( layoutGap + keycapSize / 2 + 1 * keyPitch ) - holderStemX ) + ( -2.5 mm ) - 0.5 mm ) - 0.1 mm )"
equation "d2083 = ( ( ( ( ( ( keyRowOne ) - holderStemY ) - 1.2 mm ) - 2 mm ) + faceOriginV ) + ( 4 mm ) ) - ( ( ( ( ( keyRowOne ) - holderStemY ) - 1.2 mm ) - 2 mm ) + faceOriginV )"
equation "d2084 = rearHeight"
equation "d2086 = ( ( layoutGap + keycapSize / 2 + 1 * keyPitch ) - holderStemX ) + ( 2.5 mm ) - 1.2 mm"
equation "d2087 = ( ( ( ( keyRowOne ) - holderStemY ) - 1.2 mm ) * cos(caseTilt) + ( holderBottomDepth + holderLidGap ) * sin(caseTilt) ) - 2.5 mm"
equation "d2088 = ( ( ( ( layoutGap + keycapSize / 2 + 1 * keyPitch ) - holderStemX ) + ( 2.5 mm ) - 1.2 mm ) + ( 2.4 mm ) ) - ( ( ( layoutGap + keycapSize / 2 + 1 * keyPitch ) - holderStemX ) + ( 2.5 mm ) - 1.2 mm )"
equation "d2089 = ( ( ( ( ( ( keyRowOne ) - holderStemY ) - 1.2 mm ) * cos(caseTilt) + ( holderBottomDepth + holderLidGap ) * sin(caseTilt) ) - 2.5 mm ) + ( 5 mm ) ) - ( ( ( ( ( keyRowOne ) - holderStemY ) - 1.2 mm ) * cos(caseTilt) + ( holderBottomDepth + holderLidGap ) * sin(caseTilt) ) - 2.5 mm )"
equation "d2090 = ( frontHeight + ( ( ( keyRowOne ) - holderStemY ) - 1.2 mm ) * sin(caseTilt) - ( holderBottomDepth + holderLidGap ) * cos(caseTilt) ) - bottomThickness - 2 mm"
equation "d2092 = ( ( layoutGap + keycapSize / 2 + 1 * keyPitch ) - holderStemX ) + ( 2.5 mm ) - 0.5 mm"
equation "d2093 = ( ( ( ( keyRowOne ) - holderStemY ) - 1.2 mm ) * cos(caseTilt) + ( holderBottomDepth + holderLidGap ) * sin(caseTilt) ) - 1.5 mm"
equation "d2094 = ( ( ( ( layoutGap + keycapSize / 2 + 1 * keyPitch ) - holderStemX ) + ( 2.5 mm ) - 0.5 mm ) + ( 1 mm ) ) - ( ( ( layoutGap + keycapSize / 2 + 1 * keyPitch ) - holderStemX ) + ( 2.5 mm ) - 0.5 mm )"
equation "d2095 = ( ( ( ( ( ( keyRowOne ) - holderStemY ) - 1.2 mm ) * cos(caseTilt) + ( holderBottomDepth + holderLidGap ) * sin(caseTilt) ) - 1.5 mm ) + ( 3 mm ) ) - ( ( ( ( ( keyRowOne ) - holderStemY ) - 1.2 mm ) * cos(caseTilt) + ( holderBottomDepth + holderLidGap ) * sin(caseTilt) ) - 1.5 mm )"
equation "d2096 = ( frontHeight + ( ( ( keyRowOne ) - holderStemY ) - 1.2 mm ) * sin(caseTilt) - ( holderBottomDepth + holderLidGap ) * cos(caseTilt) ) - bottomThickness + 0.5 mm"
equation "d2098 = ( ( ( layoutGap + keycapSize / 2 + 1 * keyPitch ) - holderStemX ) + ( 2.5 mm ) - 0.5 mm ) - 0.1 mm"
equation "d2099 = ( ( ( ( keyRowOne ) - holderStemY ) - 1.2 mm ) - 2 mm ) + faceOriginV"
equation "d2100 = ( ( ( ( ( layoutGap + keycapSize / 2 + 1 * keyPitch ) - holderStemX ) + ( 2.5 mm ) - 0.5 mm ) - 0.1 mm ) + ( 1.2 mm ) ) - ( ( ( ( layoutGap + keycapSize / 2 + 1 * keyPitch ) - holderStemX ) + ( 2.5 mm ) - 0.5 mm ) - 0.1 mm )"
equation "d2101 = ( ( ( ( ( ( keyRowOne ) - holderStemY ) - 1.2 mm ) - 2 mm ) + faceOriginV ) + ( 4 mm ) ) - ( ( ( ( ( keyRowOne ) - holderStemY ) - 1.2 mm ) - 2 mm ) + faceOriginV )"
equation "d2102 = rearHeight"
equation "d2104 = ( layoutGap + keycapSize / 2 + 2 * keyPitch ) - holderFrameX / 2"
equation "d2105 = ( ( keyRowOne ) - holderFrameY / 2 ) + faceOriginV"
equation "d2106 = ( ( ( layoutGap + keycapSize / 2 + 2 * keyPitch ) - holderFrameX / 2 ) + ( holderFrameX ) ) - ( ( layoutGap + keycapSize / 2 + 2 * keyPitch ) - holderFrameX / 2 )"
equation "d2107 = ( ( ( ( keyRowOne ) - holderFrameY / 2 ) + faceOriginV ) + ( holderFrameY ) ) - ( ( ( keyRowOne ) - holderFrameY / 2 ) + faceOriginV )"
equation "d2108 = -( holderBottomDepth + holderHookThickness - shellWall - carrierClearance - carrierThickness )"
equation "d2110 = ( layoutGap + keycapSize / 2 + 2 * keyPitch ) - holderSwitchVoid / 2"
equation "d2111 = ( ( keyRowOne ) - holderSwitchVoid / 2 ) + faceOriginV"
equation "d2112 = ( ( ( layoutGap + keycapSize / 2 + 2 * keyPitch ) - holderSwitchVoid / 2 ) + ( holderSwitchVoid ) ) - ( ( layoutGap + keycapSize / 2 + 2 * keyPitch ) - holderSwitchVoid / 2 )"
equation "d2113 = ( ( ( ( keyRowOne ) - holderSwitchVoid / 2 ) + faceOriginV ) + ( holderSwitchVoid ) ) - ( ( ( keyRowOne ) - holderSwitchVoid / 2 ) + faceOriginV )"
equation "d2114 = -( holderTopDepth - shellWall - carrierClearance - carrierThickness )"
equation "d2116 = ( ( layoutGap + keycapSize / 2 + 2 * keyPitch ) - holderStemX ) - holderWidth / 2 - holderFit"
equation "d2117 = ( ( ( keyRowOne ) - holderStemY ) - holderLength / 2 - holderFit ) + faceOriginV"
equation "d2118 = ( ( ( ( layoutGap + keycapSize / 2 + 2 * keyPitch ) - holderStemX ) - holderWidth / 2 - holderFit ) + ( holderWidth + 2 * holderFit ) ) - ( ( ( layoutGap + keycapSize / 2 + 2 * keyPitch ) - holderStemX ) - holderWidth / 2 - holderFit )"
equation "d2119 = ( ( ( ( ( keyRowOne ) - holderStemY ) - holderLength / 2 - holderFit ) + faceOriginV ) + ( holderLength + 2 * holderFit ) ) - ( ( ( ( keyRowOne ) - holderStemY ) - holderLength / 2 - holderFit ) + faceOriginV )"
equation "d2120 = -( holderHeight + holderHookThickness + 0.2 mm )"
equation "d2122 = ( ( layoutGap + keycapSize / 2 + 2 * keyPitch ) - holderStemX ) - holderFrameX / 2 - 0.1 mm"
equation "d2123 = ( ( ( ( keyRowOne ) - holderStemY ) + holderSpringY ) - holderSpringWidth / 2 - 0.6 mm ) + faceOriginV"
equation "d2124 = ( ( ( ( layoutGap + keycapSize / 2 + 2 * keyPitch ) - holderStemX ) - holderFrameX / 2 - 0.1 mm ) + ( holderFrameX / 2 - holderWidth / 2 - holderFit + 0.1 mm ) ) - ( ( ( layoutGap + keycapSize / 2 + 2 * keyPitch ) - holderStemX ) - holderFrameX / 2 - 0.1 mm )"
equation "d2125 = ( ( ( ( ( ( keyRowOne ) - holderStemY ) + holderSpringY ) - holderSpringWidth / 2 - 0.6 mm ) + faceOriginV ) + ( 0.6 mm ) ) - ( ( ( ( ( keyRowOne ) - holderStemY ) + holderSpringY ) - holderSpringWidth / 2 - 0.6 mm ) + faceOriginV )"
equation "d2126 = -( holderBottomDepth + holderHookThickness - shellWall - carrierClearance - carrierThickness - 1 mm + 0.2 mm )"
equation "d2128 = ( ( layoutGap + keycapSize / 2 + 2 * keyPitch ) - holderStemX ) - holderFrameX / 2 - 0.1 mm"
equation "d2129 = ( ( ( ( keyRowOne ) - holderStemY ) + holderSpringY ) + holderSpringWidth / 2 ) + faceOriginV"
equation "d2130 = ( ( ( ( layoutGap + keycapSize / 2 + 2 * keyPitch ) - holderStemX ) - holderFrameX / 2 - 0.1 mm ) + ( holderFrameX / 2 - holderWidth / 2 - holderFit + 0.1 mm ) ) - ( ( ( layoutGap + keycapSize / 2 + 2 * keyPitch ) - holderStemX ) - holderFrameX / 2 - 0.1 mm )"
equation "d2131 = ( ( ( ( ( ( keyRowOne ) - holderStemY ) + holderSpringY ) + holderSpringWidth / 2 ) + faceOriginV ) + ( 0.6 mm ) ) - ( ( ( ( ( keyRowOne ) - holderStemY ) + holderSpringY ) + holderSpringWidth / 2 ) + faceOriginV )"
equation "d2132 = -( holderBottomDepth + holderHookThickness - shellWall - carrierClearance - carrierThickness - 1 mm + 0.2 mm )"
equation "d2134 = ( ( layoutGap + keycapSize / 2 + 2 * keyPitch ) - holderStemX ) - holderFrameX / 2 + 0.8 mm"
equation "d2135 = ( ( ( ( keyRowOne ) - holderStemY ) + holderSpringY ) - holderSpringWidth / 2 ) + faceOriginV"
equation "d2136 = ( ( ( ( layoutGap + keycapSize / 2 + 2 * keyPitch ) - holderStemX ) - holderFrameX / 2 + 0.8 mm ) + ( holderFrameX / 2 - 0.8 mm - holderWidth / 2 - holderFit ) ) - ( ( ( layoutGap + keycapSize / 2 + 2 * keyPitch ) - holderStemX ) - holderFrameX / 2 + 0.8 mm )"
equation "d2137 = ( ( ( ( ( ( keyRowOne ) - holderStemY ) + holderSpringY ) - holderSpringWidth / 2 ) + faceOriginV ) + ( holderSpringWidth ) ) - ( ( ( ( ( keyRowOne ) - holderStemY ) + holderSpringY ) - holderSpringWidth / 2 ) + faceOriginV )"
equation "d2138 = -( holderHeight + holderHookThickness + 0.2 mm )"
equation "d2140 = ( ( layoutGap + keycapSize / 2 + 2 * keyPitch ) - holderStemX ) - holderFrameX / 2"
equation "d2141 = ( ( ( ( keyRowOne ) - holderStemY ) + holderSpringY ) - holderSpringWidth / 2 ) + faceOriginV"
equation "d2142 = ( ( ( ( layoutGap + keycapSize / 2 + 2 * keyPitch ) - holderStemX ) - holderFrameX / 2 ) + ( holderFrameX / 2 - holderWidth / 2 + holderHookOverlap ) ) - ( ( ( layoutGap + keycapSize / 2 + 2 * keyPitch ) - holderStemX ) - holderFrameX / 2 )"
equation "d2143 = ( ( ( ( ( ( keyRowOne ) - holderStemY ) + holderSpringY ) - holderSpringWidth / 2 ) + faceOriginV ) + ( holderSpringWidth ) ) - ( ( ( ( ( keyRowOne ) - holderStemY ) + holderSpringY ) - holderSpringWidth / 2 ) + faceOriginV )"
equation "d2144 = -( holderHookThickness )"
equation "d2147 = ( ( layoutGap + keycapSize / 2 + 2 * keyPitch ) - holderStemX ) + holderWidth / 2 + holderFit"
equation "d2148 = ( ( ( ( keyRowOne ) - holderStemY ) + holderSpringY ) - holderSpringWidth / 2 - 0.6 mm ) + faceOriginV"
equation "d2149 = ( ( ( ( layoutGap + keycapSize / 2 + 2 * keyPitch ) - holderStemX ) + holderWidth / 2 + holderFit ) + ( holderFrameX / 2 - holderWidth / 2 - holderFit + 0.1 mm ) ) - ( ( ( layoutGap + keycapSize / 2 + 2 * keyPitch ) - holderStemX ) + holderWidth / 2 + holderFit )"
equation "d2150 = ( ( ( ( ( ( keyRowOne ) - holderStemY ) + holderSpringY ) - holderSpringWidth / 2 - 0.6 mm ) + faceOriginV ) + ( 0.6 mm ) ) - ( ( ( ( ( keyRowOne ) - holderStemY ) + holderSpringY ) - holderSpringWidth / 2 - 0.6 mm ) + faceOriginV )"
equation "d2151 = -( holderBottomDepth + holderHookThickness - shellWall - carrierClearance - carrierThickness - 1 mm + 0.2 mm )"
equation "d2153 = ( ( layoutGap + keycapSize / 2 + 2 * keyPitch ) - holderStemX ) + holderWidth / 2 + holderFit"
equation "d2154 = ( ( ( ( keyRowOne ) - holderStemY ) + holderSpringY ) + holderSpringWidth / 2 ) + faceOriginV"
equation "d2155 = ( ( ( ( layoutGap + keycapSize / 2 + 2 * keyPitch ) - holderStemX ) + holderWidth / 2 + holderFit ) + ( holderFrameX / 2 - holderWidth / 2 - holderFit + 0.1 mm ) ) - ( ( ( layoutGap + keycapSize / 2 + 2 * keyPitch ) - holderStemX ) + holderWidth / 2 + holderFit )"
equation "d2156 = ( ( ( ( ( ( keyRowOne ) - holderStemY ) + holderSpringY ) + holderSpringWidth / 2 ) + faceOriginV ) + ( 0.6 mm ) ) - ( ( ( ( ( keyRowOne ) - holderStemY ) + holderSpringY ) + holderSpringWidth / 2 ) + faceOriginV )"
equation "d2157 = -( holderBottomDepth + holderHookThickness - shellWall - carrierClearance - carrierThickness - 1 mm + 0.2 mm )"
equation "d2159 = ( ( layoutGap + keycapSize / 2 + 2 * keyPitch ) - holderStemX ) + holderWidth / 2 + holderFit"
equation "d2160 = ( ( ( ( keyRowOne ) - holderStemY ) + holderSpringY ) - holderSpringWidth / 2 ) + faceOriginV"
equation "d2161 = ( ( ( ( layoutGap + keycapSize / 2 + 2 * keyPitch ) - holderStemX ) + holderWidth / 2 + holderFit ) + ( holderFrameX / 2 - 0.8 mm - holderWidth / 2 - holderFit ) ) - ( ( ( layoutGap + keycapSize / 2 + 2 * keyPitch ) - holderStemX ) + holderWidth / 2 + holderFit )"
equation "d2162 = ( ( ( ( ( ( keyRowOne ) - holderStemY ) + holderSpringY ) - holderSpringWidth / 2 ) + faceOriginV ) + ( holderSpringWidth ) ) - ( ( ( ( ( keyRowOne ) - holderStemY ) + holderSpringY ) - holderSpringWidth / 2 ) + faceOriginV )"
equation "d2163 = -( holderHeight + holderHookThickness + 0.2 mm )"
equation "d2165 = ( ( layoutGap + keycapSize / 2 + 2 * keyPitch ) - holderStemX ) + holderWidth / 2 - holderHookOverlap"
equation "d2166 = ( ( ( ( keyRowOne ) - holderStemY ) + holderSpringY ) - holderSpringWidth / 2 ) + faceOriginV"
equation "d2167 = ( ( ( ( layoutGap + keycapSize / 2 + 2 * keyPitch ) - holderStemX ) + holderWidth / 2 - holderHookOverlap ) + ( holderFrameX / 2 - holderWidth / 2 + holderHookOverlap ) ) - ( ( ( layoutGap + keycapSize / 2 + 2 * keyPitch ) - holderStemX ) + holderWidth / 2 - holderHookOverlap )"
equation "d2168 = ( ( ( ( ( ( keyRowOne ) - holderStemY ) + holderSpringY ) - holderSpringWidth / 2 ) + faceOriginV ) + ( holderSpringWidth ) ) - ( ( ( ( ( keyRowOne ) - holderStemY ) + holderSpringY ) - holderSpringWidth / 2 ) + faceOriginV )"
equation "d2169 = -( holderHookThickness )"
equation "d2172 = ( ( layoutGap + keycapSize / 2 + 2 * keyPitch ) - holderStemX ) + ( -3 mm ) - 0.5 mm"
equation "d2173 = ( ( ( keyRowOne ) - holderStemY ) + 4 mm ) + faceOriginV"
equation "d2174 = ( ( ( ( layoutGap + keycapSize / 2 + 2 * keyPitch ) - holderStemX ) + ( -3 mm ) - 0.5 mm ) + ( 1 mm ) ) - ( ( ( layoutGap + keycapSize / 2 + 2 * keyPitch ) - holderStemX ) + ( -3 mm ) - 0.5 mm )"
equation "d2175 = ( ( ( ( ( keyRowOne ) - holderStemY ) + 4 mm ) + faceOriginV ) + ( holderFrameY / 2 - 4 mm ) ) - ( ( ( ( keyRowOne ) - holderStemY ) + 4 mm ) + faceOriginV )"
equation "d2178 = ( ( layoutGap + keycapSize / 2 + 2 * keyPitch ) - holderStemX ) + ( 3 mm ) - 0.5 mm"
equation "d2179 = ( ( ( keyRowOne ) - holderStemY ) + 4 mm ) + faceOriginV"
equation "d2180 = ( ( ( ( layoutGap + keycapSize / 2 + 2 * keyPitch ) - holderStemX ) + ( 3 mm ) - 0.5 mm ) + ( 1 mm ) ) - ( ( ( layoutGap + keycapSize / 2 + 2 * keyPitch ) - holderStemX ) + ( 3 mm ) - 0.5 mm )"
equation "d2181 = ( ( ( ( ( keyRowOne ) - holderStemY ) + 4 mm ) + faceOriginV ) + ( holderFrameY / 2 - 4 mm ) ) - ( ( ( ( keyRowOne ) - holderStemY ) + 4 mm ) + faceOriginV )"
equation "d2184 = ( ( layoutGap + keycapSize / 2 + 2 * keyPitch ) - holderStemX ) - holderFrameX / 2 - 0.1 mm"
equation "d2185 = ( ( ( keyRowOne ) - holderStemY ) - 5.1 mm ) + faceOriginV"
equation "d2186 = ( ( ( ( layoutGap + keycapSize / 2 + 2 * keyPitch ) - holderStemX ) - holderFrameX / 2 - 0.1 mm ) + ( holderFrameX / 2 - holderWidth / 2 + 0.1 mm ) ) - ( ( ( layoutGap + keycapSize / 2 + 2 * keyPitch ) - holderStemX ) - holderFrameX / 2 - 0.1 mm )"
equation "d2187 = ( ( ( ( ( keyRowOne ) - holderStemY ) - 5.1 mm ) + faceOriginV ) + ( 7.8 mm ) ) - ( ( ( ( keyRowOne ) - holderStemY ) - 5.1 mm ) + faceOriginV )"
equation "d2188 = -( holderHeight + holderHookThickness - 1.2 mm + 0.2 mm )"
equation "d2190 = ( ( layoutGap + keycapSize / 2 + 2 * keyPitch ) - holderStemX ) + holderWidth / 2"
equation "d2191 = ( ( ( keyRowOne ) - holderStemY ) - 5.1 mm ) + faceOriginV"
equation "d2192 = ( ( ( ( layoutGap + keycapSize / 2 + 2 * keyPitch ) - holderStemX ) + holderWidth / 2 ) + ( holderFrameX / 2 - holderWidth / 2 + 0.1 mm ) ) - ( ( ( layoutGap + keycapSize / 2 + 2 * keyPitch ) - holderStemX ) + holderWidth / 2 )"
equation "d2193 = ( ( ( ( ( keyRowOne ) - holderStemY ) - 5.1 mm ) + faceOriginV ) + ( 7.8 mm ) ) - ( ( ( ( keyRowOne ) - holderStemY ) - 5.1 mm ) + faceOriginV )"
equation "d2194 = -( holderHeight + holderHookThickness - 1.2 mm + 0.2 mm )"
equation "d2196 = ( ( layoutGap + keycapSize / 2 + 2 * keyPitch ) - holderStemX ) + ( -2.5 mm ) - 1.2 mm"
equation "d2197 = ( ( ( ( keyRowOne ) - holderStemY ) - 1.2 mm ) * cos(caseTilt) + ( holderBottomDepth + holderLidGap ) * sin(caseTilt) ) - 2.5 mm"
equation "d2198 = ( ( ( ( layoutGap + keycapSize / 2 + 2 * keyPitch ) - holderStemX ) + ( -2.5 mm ) - 1.2 mm ) + ( 2.4 mm ) ) - ( ( ( layoutGap + keycapSize / 2 + 2 * keyPitch ) - holderStemX ) + ( -2.5 mm ) - 1.2 mm )"
equation "d2199 = ( ( ( ( ( ( keyRowOne ) - holderStemY ) - 1.2 mm ) * cos(caseTilt) + ( holderBottomDepth + holderLidGap ) * sin(caseTilt) ) - 2.5 mm ) + ( 5 mm ) ) - ( ( ( ( ( keyRowOne ) - holderStemY ) - 1.2 mm ) * cos(caseTilt) + ( holderBottomDepth + holderLidGap ) * sin(caseTilt) ) - 2.5 mm )"
equation "d2200 = ( frontHeight + ( ( ( keyRowOne ) - holderStemY ) - 1.2 mm ) * sin(caseTilt) - ( holderBottomDepth + holderLidGap ) * cos(caseTilt) ) - bottomThickness - 2 mm"
equation "d2202 = ( ( layoutGap + keycapSize / 2 + 2 * keyPitch ) - holderStemX ) + ( -2.5 mm ) - 0.5 mm"
equation "d2203 = ( ( ( ( keyRowOne ) - holderStemY ) - 1.2 mm ) * cos(caseTilt) + ( holderBottomDepth + holderLidGap ) * sin(caseTilt) ) - 1.5 mm"
equation "d2204 = ( ( ( ( layoutGap + keycapSize / 2 + 2 * keyPitch ) - holderStemX ) + ( -2.5 mm ) - 0.5 mm ) + ( 1 mm ) ) - ( ( ( layoutGap + keycapSize / 2 + 2 * keyPitch ) - holderStemX ) + ( -2.5 mm ) - 0.5 mm )"
equation "d2205 = ( ( ( ( ( ( keyRowOne ) - holderStemY ) - 1.2 mm ) * cos(caseTilt) + ( holderBottomDepth + holderLidGap ) * sin(caseTilt) ) - 1.5 mm ) + ( 3 mm ) ) - ( ( ( ( ( keyRowOne ) - holderStemY ) - 1.2 mm ) * cos(caseTilt) + ( holderBottomDepth + holderLidGap ) * sin(caseTilt) ) - 1.5 mm )"
equation "d2206 = ( frontHeight + ( ( ( keyRowOne ) - holderStemY ) - 1.2 mm ) * sin(caseTilt) - ( holderBottomDepth + holderLidGap ) * cos(caseTilt) ) - bottomThickness + 0.5 mm"
equation "d2208 = ( ( ( layoutGap + keycapSize / 2 + 2 * keyPitch ) - holderStemX ) + ( -2.5 mm ) - 0.5 mm ) - 0.1 mm"
equation "d2209 = ( ( ( ( keyRowOne ) - holderStemY ) - 1.2 mm ) - 2 mm ) + faceOriginV"
equation "d2210 = ( ( ( ( ( layoutGap + keycapSize / 2 + 2 * keyPitch ) - holderStemX ) + ( -2.5 mm ) - 0.5 mm ) - 0.1 mm ) + ( 1.2 mm ) ) - ( ( ( ( layoutGap + keycapSize / 2 + 2 * keyPitch ) - holderStemX ) + ( -2.5 mm ) - 0.5 mm ) - 0.1 mm )"
equation "d2211 = ( ( ( ( ( ( keyRowOne ) - holderStemY ) - 1.2 mm ) - 2 mm ) + faceOriginV ) + ( 4 mm ) ) - ( ( ( ( ( keyRowOne ) - holderStemY ) - 1.2 mm ) - 2 mm ) + faceOriginV )"
equation "d2212 = rearHeight"
equation "d2214 = ( ( layoutGap + keycapSize / 2 + 2 * keyPitch ) - holderStemX ) + ( 2.5 mm ) - 1.2 mm"
equation "d2215 = ( ( ( ( keyRowOne ) - holderStemY ) - 1.2 mm ) * cos(caseTilt) + ( holderBottomDepth + holderLidGap ) * sin(caseTilt) ) - 2.5 mm"
equation "d2216 = ( ( ( ( layoutGap + keycapSize / 2 + 2 * keyPitch ) - holderStemX ) + ( 2.5 mm ) - 1.2 mm ) + ( 2.4 mm ) ) - ( ( ( layoutGap + keycapSize / 2 + 2 * keyPitch ) - holderStemX ) + ( 2.5 mm ) - 1.2 mm )"
equation "d2217 = ( ( ( ( ( ( keyRowOne ) - holderStemY ) - 1.2 mm ) * cos(caseTilt) + ( holderBottomDepth + holderLidGap ) * sin(caseTilt) ) - 2.5 mm ) + ( 5 mm ) ) - ( ( ( ( ( keyRowOne ) - holderStemY ) - 1.2 mm ) * cos(caseTilt) + ( holderBottomDepth + holderLidGap ) * sin(caseTilt) ) - 2.5 mm )"
equation "d2218 = ( frontHeight + ( ( ( keyRowOne ) - holderStemY ) - 1.2 mm ) * sin(caseTilt) - ( holderBottomDepth + holderLidGap ) * cos(caseTilt) ) - bottomThickness - 2 mm"